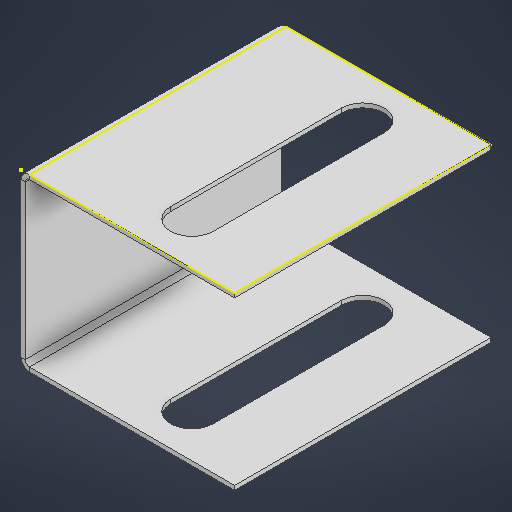
# Autodesk Inventor part: 22.10.2025-b3
Saved by Autodesk Inventor 2026.1 (Build 301233020, 233B)
## iProperties
Created: 2026-01-09
Part Number: 22.10.2025-b3
Material: Ogólny
Document SubType Name: Sheet Metal
Designer: Nitro
Density: 1 g/cm^3
Flat Pattern Width: 3 cm
Flat Pattern Length: 6.82619 cm
Flat Pattern Area: 20.4786 cm^2
Sheet Metal Rule: Domyślny_mm
Sheet Metal Width: 30,000 mm
Sheet Metal Length: 68,262 mm
Sheet Metal Area: 2047,858 mm^2
Appearance: Domyślna
Author: Nitro
Autodesk Inventor part; units mm, degrees
ref_plane "YZ Plane" through (0, 0, 0) normal (1, 0, 0) x (0, 1, 0)
ref_plane "XZ Plane" through (0, 0, 0) normal (0, 1, 0) x (-1, 0, 0)
ref_plane "XY Plane" through (0, 0, 0) normal (0, 0, 1) x (1, 0, 0)
sketch "Szkic1" plane through (0, 0, 0) normal (1, 0, 0) x (0, 1, 0)
  line L0 (0, 0) -> (20, 0)
  line L1 (20, 0) -> (20, -30)
  line L2 (20, -30) -> (0, -30)
  line L3 (0, -30) -> (0, 0)
  dimension "d0" = 20
  dimension "d1" = 30
  measures "d0" distance of L1.end L2.end
  measures "d1" distance of L0.end L1.end
extrude "Płyta1" add sketch "Szkic1" along normal blind 0.5
sketch "Szkic2" plane through (0, 19.5, 0) normal (0, 1, 0) x (-1, 0, 0)
  line L0 (0, -30) -> (0, 0)
  line L1 (0, 0) -> (-25, 0)
  line L2 (-25, 0) -> (-25, -30)
  line L3 (-25, -30) -> (0, -30)
  constraints: 6 end point, 1 horizontal, 1 perpendicular, 1 vertical
edge flange "Kołnierz1" height 25 angle 90 thickness 0.5 bend radius 0.5 thickness toward (0, 1, 0) relief tear relief width 0.5 relief depth 0.25 corner gap 0.5 corner form 0 edges at (0.5, 20, -15) (0.5, 0, -15) wall of the first edge with corners at (0, 19.5, -30) (0, 19.5, 0) (25, 19.5, 0) (25, 19.5, -30)
bend "Zagięcie1"
corner "Narożnik1"
sketch "Szkic3" plane through (25, 20, 0) normal (0, 1, 0) x (1, 0, 0)
  line L0 (-24, 30) -> (-24, 0) projected
  line L1 (0, 0) -> (-24, 0) projected
  line L2 (0, 30) -> (0, 0) projected
  line L3 (-24, 30) -> (0, 30) projected
  point P0 (-25, 0)
sketch "Szkic4" plane through (25, 20, 0) normal (0, 1, 0) x (1, 0, 0)
  line L0 (-24, 30) -> (-24, 0) projected
  line L1 (0, 0) -> (-24, 0) projected
  line L2 (0, 30) -> (0, 0) projected
  line L3 (-24, 30) -> (0, 30) projected
  line L4 (0, 5) -> (-24, 5)
  line L5 (-24, 25) -> (0, 25)
  line L6 (0, 0) -> (0, 30) projected
  line L7 (0, 30) -> (-24, 30) projected
  line L8 (-10, 30) -> (-10, 0)
  line L9 (-10, 25) -> (-10, 5) construction
  line L10 (-12.5, 25) -> (-12.5, 5)
  line L11 (-7.5, 5) -> (-7.5, 25)
  arc A0 (-7.5, 25) -> (-12.5, 25) centre (-10, 25) ccw
  arc A1 (-12.5, 5) -> (-7.5, 5) centre (-10, 5) ccw
  point P0 (-25, 0)
  point P1 (-10, 15)
  dimension "d13" = 10
  dimension "d14" = 5
  dimension "d15" = 5
  dimension "d16" = 5
  constraints: 14 end point, 10 point on line, 4 point on circle, 4 tangent, 2 centre point, 2 perpendicular, 1 horizontal, 1 midpoint, 1 parallel
  measures "d13" distance between parallel lines of L2 L8
  measures "d14" distance between parallel lines of L3 L5
  measures "d15" distance between parallel lines of L1 L4
  measures "d16" diameter of A1
extrude "Wyciągnięcie proste1" cut sketch "Szkic4" against normal blind 50 contours A0 L8 L5 | L5 L8 L4 L10 | A0 L5 L8 | L4 L8 A1 | L5 L11 L4 L8 | L4 A1 L8
equation "\"d2\" = Grubość"
equation "\"d3\" = SzerokośćGięciaPodcięcia"
equation "\"d4\" = GłębokośćGięciaPodcięcia"
equation "\"d5\" = MinimalnaPozostałość"
equation "\"d6\" = PromieńPrzejścia"
equation "\"d9\" = PromieńGięcia"
equation "\"d10\" = RozmiarPodcięciaNarożnika"
equation "\"d11\" = Wielk_odstępu"
equation "\"d12\" = Rozmiar_promienia_Jacobiego"
equation "\"PromieńGięcia\" = Grubość"
equation "\"SzerokośćGięciaPodcięcia\" = Grubość"
equation "\"GłębokośćGięciaPodcięcia\" = 0.5 * Grubość"
equation "\"RozmiarPodcięciaNarożnika\" = 4 * Grubość"
equation "\"MinimalnaPozostałość\" = 2 * Grubość"
equation "\"PromieńPrzejścia\" = PromieńGięcia"
equation "\"Rozmiar_promienia_Jacobiego\" = PromieńGięcia"
equation "\"Wielk_odstępu\" = Grubość"
equation "\"Grubość\" = 0.5"
